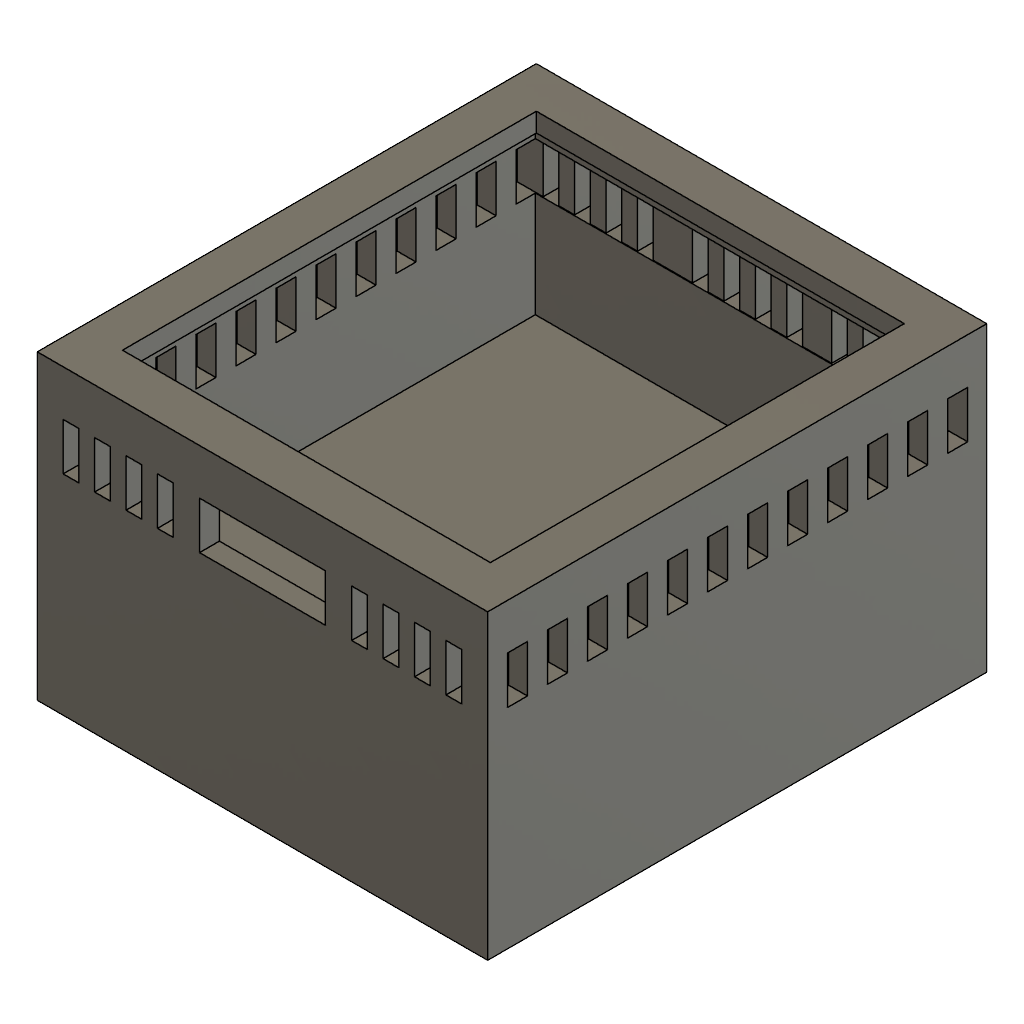
keychain dimensions (Autodesk Fusion 360 design; units mm, degrees)
part number: 2026-11-23-17-55-54-505
Autodesk Fusion 360 part; units mm, degrees
sketch "Sketch1" plane through (0, 0, 0) normal (0, 1, 0) x (1, 0, 0)
  line L0 (0, 0) -> (28.65, 0)
  line L1 (28.65, 0) -> (28.65, 31.75)
  line L2 (28.65, 31.75) -> (0, 31.75)
  line L3 (0, 31.75) -> (0, 0)
  dimension "d1" = 28.65
  dimension "d2" = 31.75
  constraint horizontal L0
  constraint vertical L1
  constraint horizontal L2
  constraint vertical L3
  constraint coincident L0.start L3.end
  measures "d1" distance of L1 L3
  measures "d2" distance of L0 L2
extrude "Extrude1" add sketch "Sketch1" along normal blind 18
sketch "Sketch2" plane through (0, 18, 0) normal (0, 1, 0) x (-1, 0, 0)
  line L0 (0, -31.75) -> (0, 0)
  line L1 (0, 0) -> (-28.65, 0)
  line L2 (-28.65, 0) -> (-28.65, -31.75)
  line L3 (-28.65, -31.75) -> (0, -31.75)
  line L4 (0, -31.75) -> (-1.2, -31.75)
  line L5 (-28.65, -31.75) -> (-27.45, -31.75)
  line L6 (-1.2, -31.75) -> (-1.2, -30.485)
  line L7 (-1.2, -30.485) -> (-27.45, -30.485)
  line L8 (-27.45, -30.485) -> (-27.45, -1.265)
  line L9 (-27.45, -1.265) -> (-1.2, -1.265)
  line L10 (-1.2, -1.265) -> (-1.2, -30.485)
  dimension "d5" = 1.2
  dimension "d6" = 1.2
  dimension "d7" = 1.265
  dimension "d8" = 29.22
  constraint coincident L0.start L3.end
  constraint perpendicular L0 L4
  constraint coincident L2.end L3.start
  constraint perpendicular L2 L5
  constraint perpendicular L4 L6
  constraint horizontal L7
  constraint vertical L8
  constraint horizontal L9
  constraint vertical L10
  measures "d5" distance of L0.start L4.end
  measures "d6" distance of L2.end L5.end
  measures "d7" distance of L4.end L6.end
  measures "d8" distance of L7 L9
extrude "Extrude2" cut sketch "Sketch2" against normal blind 11.4 contours L7 L8 L9 L10
sketch "Sketch3" plane through (0, 0, 0) normal (0, 0, 1) x (1, 0, 0)
  line L0 (0, 0) -> (28.65, 0)
  line L1 (28.65, 0) -> (28.65, 18)
  line L2 (28.65, 18) -> (0, 18)
  line L3 (0, 18) -> (0, 0)
  line L4 (0, 18) -> (28.65, 0)
  line L5 (0, 0) -> (28.65, 18)
  line L6 (14.325, 9) -> (14.325, 18)
  line L7 (14.325, 18) -> (14.325, 11.6)
  line L8 (14.325, 18) -> (14.325, 16.3)
  line L9 (14.325, 16.3) -> (20.6955, 16.3)
  line L10 (20.6955, 16.3) -> (20.6955, 13.3)
  line L11 (20.6955, 13.3) -> (9, 13.3)
  line L12 (14.325, 14.8) -> (18.325, 14.8)
  line L13 (14.325, 14.8) -> (10.325, 14.8)
  line L14 (18.325, 14.8) -> (18.325, 16.3)
  line L15 (18.325, 14.8) -> (18.325, 13.3)
  line L16 (10.325, 14.8) -> (10.325, 16.3)
  line L17 (10.325, 14.8) -> (10.325, 13.3)
  line L18 (14.325, 16.3) -> (10.325, 16.3)
  dimension "d11" = 6.4
  dimension "d12" = 1.7
  dimension "d13" = 3
  dimension "d14" = 4
  dimension "d15" = 4
  constraint coincident L2.end L3.start
  constraint coincident L0.end L1.start
  constraint coincident L0.start L3.end
  constraint coincident L1.end L2.start
  constraint midpoint L5 L6.start
  constraint midpoint L2 L6.end
  constraint perpendicular L2 L7
  constraint perpendicular L2 L8
  constraint perpendicular L7 L9
  constraint perpendicular L9 L10
  constraint perpendicular L10 L11
  constraint midpoint L7 L12.start
  constraint perpendicular L6 L12
  constraint perpendicular L6 L13
  constraint coincident L9 L14.end
  constraint perpendicular L9 L14
  constraint coincident L11 L15.end
  constraint perpendicular L11 L15
  constraint symmetric L7 L12.end L13.end
  constraint symmetric L7 L14.end L16.end
  constraint symmetric L7 L15.end L17.end
  measures "d11" distance of L6.end L7.end
  measures "d12" distance of L6.end L8.end
  measures "d13" distance of L9.end L10.end
  measures "d14" distance of L12.start L12.end
  measures "d15" distance of L12.start L13.end
extrude "Extrude3" cut sketch "Sketch3" against normal blind 4.5 contours L6 L7 L9 L12 L14 | L6 L7 L13 L16 L18 | L6 L7 L11 L13 L17 | L6 L7 L11 L12 L15
sketch "Sketch4" plane through (0, 18, 0) normal (0, 1, 0) x (-1, 0, 0)
  line L0 (-27.45, -30.485) -> (-27.45, -1.265)
  line L1 (-27.45, -1.265) -> (-1.2, -1.265)
  line L2 (-1.2, -1.265) -> (-1.2, -30.485)
  line L3 (-1.2, -30.485) -> (-27.45, -30.485)
  line L4 (0, -31.75) -> (0, 0)
  line L5 (0, 0) -> (-28.65, 0)
  line L6 (-28.65, 0) -> (-28.65, -31.75)
  line L7 (-28.65, -31.75) -> (0, -31.75)
  line L8 (-28.65, 0) -> (-28.65, -2.8)
  line L9 (-28.65, -2.8) -> (0, -2.8)
  line L10 (0, -2.8) -> (0, 0)
  line L11 (-28.65, 0) -> (0, 0)
  line L12 (0, 0) -> (-2.625, 0)
  line L13 (-2.625, 0) -> (-2.625, -31.75)
  line L14 (-14.325, -31.75) -> (-14.325, 9)
  line L15 (-26.025, 0) -> (-26.025, -31.75)
  line L16 (-28.65, -31.75) -> (-28.65, -29.125)
  line L17 (-28.65, -29.125) -> (0, -29.125)
  line L18 (0, -31.75) -> (-28.65, -31.75)
  line L19 (-28.65, -31.75) -> (-28.65, 0)
  line L20 (-28.65, 0) -> (0, 0)
  line L21 (0, 0) -> (0, -31.75)
  dimension "d18" = 2.8
  dimension "d19" = 2.625
  dimension "d20" = 2.625
  constraint coincident L5.end L6.start
  constraint perpendicular L5 L8
  constraint coincident L4 L9.end
  constraint perpendicular L4 L9
  constraint coincident L4.end L5.start
  constraint perpendicular L4 L12
  constraint coincident L7 L13.end
  constraint perpendicular L7 L13
  constraint midpoint L7 L14.start
  constraint perpendicular L11 L14
  constraint symmetric L12.end L14 L15.start
  constraint symmetric L13.end L14 L15.end
  constraint coincident L6.end L7.start
  constraint perpendicular L7 L16
  constraint coincident L4 L17.end
  constraint perpendicular L4 L17
  constraint horizontal L18
  constraint vertical L19
  constraint horizontal L20
  constraint vertical L21
  constraint coincident L4.start L7.end
  measures "d18" distance of L5.end L8.end
  measures "d19" distance of L4.end L12.end
  measures "d20" distance of L6.end L16.end
extrude "Extrude4" add sketch "Sketch4" along normal blind 1.2 contours L0 L3 L6 L7 L15 L16 L17 L18 L19 | L0 L3 L15 L17 | L0 L6 L9 L17 L19 | L0 L9 L15 L17 | L3 L14 L15 L17 | L3 L7 L14 L15 L18 | L0 L1 L5 L6 L8 L9 L11 L15 L19 L20 | L0 L1 L9 L15 | L3 L13 L14 L17 | L3 L7 L13 L14 L18 | L1 L9 L14 L15 | L2 L3 L13 L17 | L2 L3 L4 L7 L13 L17 L18 L21 | L1 L5 L11 L14 L15 L20 | L1 L9 L13 L14 | L2 L9 L13 L17 | L1 L5 L11 L13 L14 L20 | L1 L2 L9 L13 | L2 L4 L9 L17 L21 | L1 L2 L4 L5 L9 L10 L11 L12 L13 L20 L21
sketch "Sketch5" plane through (0, 0, 0) normal (0, 0, 1) x (1, 0, 0)
  line L0 (10.325, 16.3) -> (18.325, 16.3)
  line L1 (18.325, 16.3) -> (18.325, 13.3)
  line L2 (18.325, 13.3) -> (10.325, 13.3)
  line L3 (10.325, 13.3) -> (10.325, 16.3)
  line L4 (0, 0) -> (28.65, 0)
  line L5 (28.65, 0) -> (28.65, 19.2)
  line L6 (28.65, 19.2) -> (0, 19.2)
  line L7 (0, 19.2) -> (0, 0)
  line L8 (18.325, 14.8) -> (28.65, 14.8)
  line L9 (25, 16.3) -> (25, 13.3)
  line L10 (24, 13.3) -> (24, 16.3)
  line L11 (24, 16.3) -> (25, 16.3)
  line L12 (24, 13.3) -> (25, 13.3)
  line L13 (27, 16.3) -> (27, 13.3)
  line L14 (26, 16.3) -> (27, 16.3)
  line L15 (26, 13.3) -> (26, 16.3)
  line L16 (26, 13.3) -> (27, 13.3)
  line L17 (23, 16.3) -> (23, 13.3)
  line L18 (22, 16.3) -> (23, 16.3)
  line L19 (22, 13.3) -> (22, 16.3)
  line L20 (22, 13.3) -> (23, 13.3)
  line L21 (21, 16.3) -> (21, 13.3)
  line L22 (20, 16.3) -> (21, 16.3)
  line L23 (20, 13.3) -> (20, 16.3)
  line L24 (20, 13.3) -> (21, 13.3)
  line L25 (14.325, 19.2) -> (14.325, 0)
  line L26 (6.65, 13.3) -> (5.65, 13.3)
  line L27 (4.65, 16.3) -> (3.65, 16.3)
  line L28 (4.65, 13.3) -> (4.65, 16.3)
  line L29 (6.65, 16.3) -> (5.65, 16.3)
  line L30 (2.65, 13.3) -> (2.65, 16.3)
  line L31 (6.65, 13.3) -> (6.65, 16.3)
  line L32 (8.65, 13.3) -> (8.65, 16.3)
  line L33 (2.65, 13.3) -> (1.65, 13.3)
  line L34 (7.65, 16.3) -> (7.65, 13.3)
  line L35 (3.65, 16.3) -> (3.65, 13.3)
  line L36 (1.65, 16.3) -> (1.65, 13.3)
  line L37 (8.65, 16.3) -> (7.65, 16.3)
  line L38 (4.65, 13.3) -> (3.65, 13.3)
  line L39 (8.65, 13.3) -> (7.65, 13.3)
  line L40 (2.65, 16.3) -> (1.65, 16.3)
  line L41 (5.65, 16.3) -> (5.65, 13.3)
  dimension "d25" = -4
  dimension "d26" = 0
  constraint midpoint L1 L8.start
  constraint coincident L5 L8.end
  constraint perpendicular L5 L8
  constraint vertical L9
  constraint vertical L10
  constraint perpendicular L1 L11
  constraint perpendicular L10 L12
  constraint midpoint L6 L25.start
  constraint midpoint L4 L25.end
  constraint symmetric L10.end L25 L27.start
  constraint symmetric L9.start L25 L27.end
  constraint symmetric L10.start L25 L28.start
  constraint symmetric L9.end L25 L35.end
  constraint symmetric L13.start L25 L36.start
  constraint symmetric L13.end L25 L33.end
  constraint symmetric L14.start L25 L30.end
  constraint symmetric L15.start L25 L30.start
  constraint symmetric L17.start L25 L29.end
  constraint symmetric L17.end L25 L26.end
  constraint symmetric L18.start L25 L29.start
  constraint symmetric L19.start L25 L26.start
  constraint symmetric L21.start L25 L34.start
  constraint symmetric L21.end L25 L34.end
  constraint symmetric L22.start L25 L32.end
  constraint symmetric L23.start L25 L32.start
extrude "Extrude5" cut sketch "Sketch5" against normal blind 55 contours L8 L21 L22 L23 | L8 L21 L23 L24 | L8 L13 L15 L16 | L8 L13 L14 L15 | L8 L17 L18 L19 | L8 L17 L19 L20 | L8 L9 L10 L12 | L8 L9 L10 L11 | L26 L29 L31 L41 | L27 L28 L35 L38 | L30 L33 L36 L40 | L32 L34 L37 L39
sketch "Sketch6" plane through (0, 0, 0) normal (-1, 0, 0) x (0, 0, 1)
  line L0 (-31.75, 0) -> (0, 0)
  line L1 (0, 0) -> (0, 19.2)
  line L2 (0, 19.2) -> (-31.75, 19.2)
  line L3 (-31.75, 19.2) -> (-31.75, 0)
  line L4 (-1.265, 16.3) -> (-1.265, 13.3)
  line L5 (-1.265, 13.3) -> (0, 13.3)
  line L6 (0, 13.3) -> (0, 16.3)
  line L7 (0, 16.3) -> (-1.265, 16.3)
  line L8 (-1.265, 16.3) -> (0, 16.3)
  line L9 (0, 16.3) -> (0, 13.3)
  line L10 (0, 13.3) -> (-1.265, 13.3)
  line L11 (-1.265, 13.3) -> (-1.265, 16.3)
  line L12 (-1.265, 13.3) -> (-2.53, 13.3)
  line L13 (-2.53, 13.3) -> (-2.53, 16.3)
  line L14 (-2.53, 16.3) -> (-1.265, 16.3)
  line L15 (-1.265, 16.3) -> (-1.265, 13.3)
  line L16 (-2.53, 14.8) -> (-32, 14.8)
  line L17 (-1.265, 16.3) -> (-1.265, 13.3)
  line L18 (-3.8105, 16.3) -> (-3.8105, 13.3)
  line L19 (-5.0755, 16.3) -> (-3.8105, 16.3)
  line L20 (-5.0755, 13.3) -> (-5.0755, 16.3)
  line L21 (-3.8105, 13.3) -> (-5.0755, 13.3)
  line L22 (-6.3559, 16.3) -> (-6.3559, 13.3)
  line L23 (-7.6209, 16.3) -> (-6.3559, 16.3)
  line L24 (-7.6209, 13.3) -> (-7.6209, 16.3)
  line L25 (-6.3559, 13.3) -> (-7.6209, 13.3)
  line L26 (-8.9014, 16.3) -> (-8.9014, 13.3)
  line L27 (-10.1664, 16.3) -> (-8.9014, 16.3)
  line L28 (-10.1664, 13.3) -> (-10.1664, 16.3)
  line L29 (-8.9014, 13.3) -> (-10.1664, 13.3)
  line L30 (-11.4468, 16.3) -> (-11.4468, 13.3)
  line L31 (-12.7118, 16.3) -> (-11.4468, 16.3)
  line L32 (-12.7118, 13.3) -> (-12.7118, 16.3)
  line L33 (-11.4468, 13.3) -> (-12.7118, 13.3)
  line L34 (-13.9923, 16.3) -> (-13.9923, 13.3)
  line L35 (-15.2573, 16.3) -> (-13.9923, 16.3)
  line L36 (-15.2573, 13.3) -> (-15.2573, 16.3)
  line L37 (-13.9923, 13.3) -> (-15.2573, 13.3)
  line L38 (-16.5377, 16.3) -> (-16.5377, 13.3)
  line L39 (-17.8027, 16.3) -> (-16.5377, 16.3)
  line L40 (-17.8027, 13.3) -> (-17.8027, 16.3)
  line L41 (-16.5377, 13.3) -> (-17.8027, 13.3)
  line L42 (-19.0832, 16.3) -> (-19.0832, 13.3)
  line L43 (-20.3482, 16.3) -> (-19.0832, 16.3)
  line L44 (-20.3482, 13.3) -> (-20.3482, 16.3)
  line L45 (-19.0832, 13.3) -> (-20.3482, 13.3)
  line L46 (-21.6286, 16.3) -> (-21.6286, 13.3)
  line L47 (-22.8936, 16.3) -> (-21.6286, 16.3)
  line L48 (-22.8936, 13.3) -> (-22.8936, 16.3)
  line L49 (-21.6286, 13.3) -> (-22.8936, 13.3)
  line L50 (-24.1741, 16.3) -> (-24.1741, 13.3)
  line L51 (-25.4391, 16.3) -> (-24.1741, 16.3)
  line L52 (-25.4391, 13.3) -> (-25.4391, 16.3)
  line L53 (-24.1741, 13.3) -> (-25.4391, 13.3)
  line L54 (-26.7195, 16.3) -> (-26.7195, 13.3)
  line L55 (-27.9845, 16.3) -> (-26.7195, 16.3)
  line L56 (-27.9845, 13.3) -> (-27.9845, 16.3)
  line L57 (-26.7195, 13.3) -> (-27.9845, 13.3)
  line L58 (-29.265, 16.3) -> (-29.265, 13.3)
  line L59 (-30.53, 16.3) -> (-29.265, 16.3)
  line L60 (-30.53, 13.3) -> (-30.53, 16.3)
  line L61 (-29.265, 13.3) -> (-30.53, 13.3)
  dimension "d29" = 1.265
  dimension "d32" = -28
  dimension "d33" = 0
  constraint horizontal L8
  constraint vertical L9
  constraint horizontal L10
  constraint vertical L11
  constraint coincident L5.end L6.start
  constraint coincident L4.start L7.end
  constraint horizontal L12
  constraint vertical L13
  constraint horizontal L14
  constraint vertical L15
  constraint coincident L4.end L5.start
  constraint midpoint L13 L16.start
  constraint perpendicular L3 L16
  measures "d29" distance of L11 L13
extrude "Extrude6" cut sketch "Sketch6" against normal blind 59 contours L16 L58 L59 L60 | L16 L58 L60 L61 | L4 L11 L12 L13 L14 L15 L17 | L16 L54 L55 L56 | L16 L54 L56 L57 | L16 L18 L20 L21 | L16 L18 L19 L20 | L16 L50 L51 L52 | L16 L50 L52 L53 | L16 L22 L24 L25 | L16 L22 L23 L24 | L16 L46 L47 L48 | L16 L46 L48 L49 | L16 L26 L28 L29 | L16 L26 L27 L28 | L16 L42 L43 L44 | L16 L42 L44 L45 | L16 L30 L32 L33 | L16 L30 L31 L32 | L16 L38 L39 L40 | L16 L38 L40 L41 | L16 L34 L36 L37 | L16 L34 L35 L36
sketch "Sketch7" plane through (0, 0, -31.75) normal (0, 0, -1) x (-1, 0, 0)
  line L0 (-28.65, 0) -> (0, 0)
  line L1 (0, 0) -> (0, 19.2)
  line L2 (0, 19.2) -> (-28.65, 19.2)
  line L3 (-28.65, 19.2) -> (-28.65, 0)
  line L4 (-26, 13.3) -> (-27, 13.3)
  line L5 (-27, 13.3) -> (-27, 16.3)
  line L6 (-27, 16.3) -> (-26, 16.3)
  line L7 (-26, 16.3) -> (-26, 13.3)
  line L8 (-7.65, 16.3) -> (-7.65, 13.3)
  line L9 (-7.65, 13.3) -> (-8.65, 13.3)
  line L10 (-8.65, 13.3) -> (-8.65, 16.3)
  line L11 (-8.65, 16.3) -> (-7.65, 16.3)
  line L12 (-2.65, 16.3) -> (-1.65, 16.3)
  line L13 (-1.65, 16.3) -> (-1.65, 13.3)
  line L14 (-1.65, 13.3) -> (-2.65, 13.3)
  line L15 (-2.65, 13.3) -> (-2.65, 16.3)
  line L16 (-20, 13.3) -> (-21, 13.3)
  line L17 (-21, 13.3) -> (-21, 16.3)
  line L18 (-21, 16.3) -> (-20, 16.3)
  line L19 (-20, 16.3) -> (-20, 13.3)
  line L20 (-24, 13.3) -> (-25, 13.3)
  line L21 (-25, 13.3) -> (-25, 16.3)
  line L22 (-25, 16.3) -> (-24, 16.3)
  line L23 (-24, 16.3) -> (-24, 13.3)
  line L24 (-6.65, 16.3) -> (-5.65, 16.3)
  line L25 (-5.65, 16.3) -> (-5.65, 13.3)
  line L26 (-5.65, 13.3) -> (-6.65, 13.3)
  line L27 (-6.65, 13.3) -> (-6.65, 16.3)
  line L28 (-3.65, 16.3) -> (-3.65, 13.3)
  line L29 (-3.65, 13.3) -> (-4.65, 13.3)
  line L30 (-4.65, 13.3) -> (-4.65, 16.3)
  line L31 (-4.65, 16.3) -> (-3.65, 16.3)
  line L32 (-22, 13.3) -> (-23, 13.3)
  line L33 (-23, 13.3) -> (-23, 16.3)
  line L34 (-23, 16.3) -> (-22, 16.3)
  line L35 (-22, 16.3) -> (-22, 13.3)
  line L36 (-14.15, 13.3) -> (-14.15, 16.3)
  line L37 (-14.15, 16.3) -> (-13.15, 16.3)
  line L38 (-12.15, 16.3) -> (-11.15, 16.3)
  line L39 (-18.15, 16.3) -> (-17.15, 16.3)
  line L40 (-15.15, 16.3) -> (-15.15, 13.3)
  line L41 (-15.15, 13.3) -> (-16.15, 13.3)
  line L42 (-17.15, 16.3) -> (-17.15, 13.3)
  line L43 (-18.15, 13.3) -> (-18.15, 16.3)
  line L44 (-11.15, 16.3) -> (-11.15, 13.3)
  line L45 (-13.15, 16.3) -> (-13.15, 13.3)
  line L46 (-12.15, 13.3) -> (-12.15, 16.3)
  line L47 (-13.15, 13.3) -> (-14.15, 13.3)
  line L48 (-11.15, 13.3) -> (-12.15, 13.3)
  line L49 (-16.15, 16.3) -> (-15.15, 16.3)
  line L50 (-16.15, 13.3) -> (-16.15, 16.3)
  line L51 (-17.15, 13.3) -> (-18.15, 13.3)
extrude "Extrude7" cut sketch "Sketch7" against normal blind 12 contours L36 L37 L45 L47 | L38 L44 L46 L48 | L39 L42 L43 L51 | L40 L41 L49 L50
